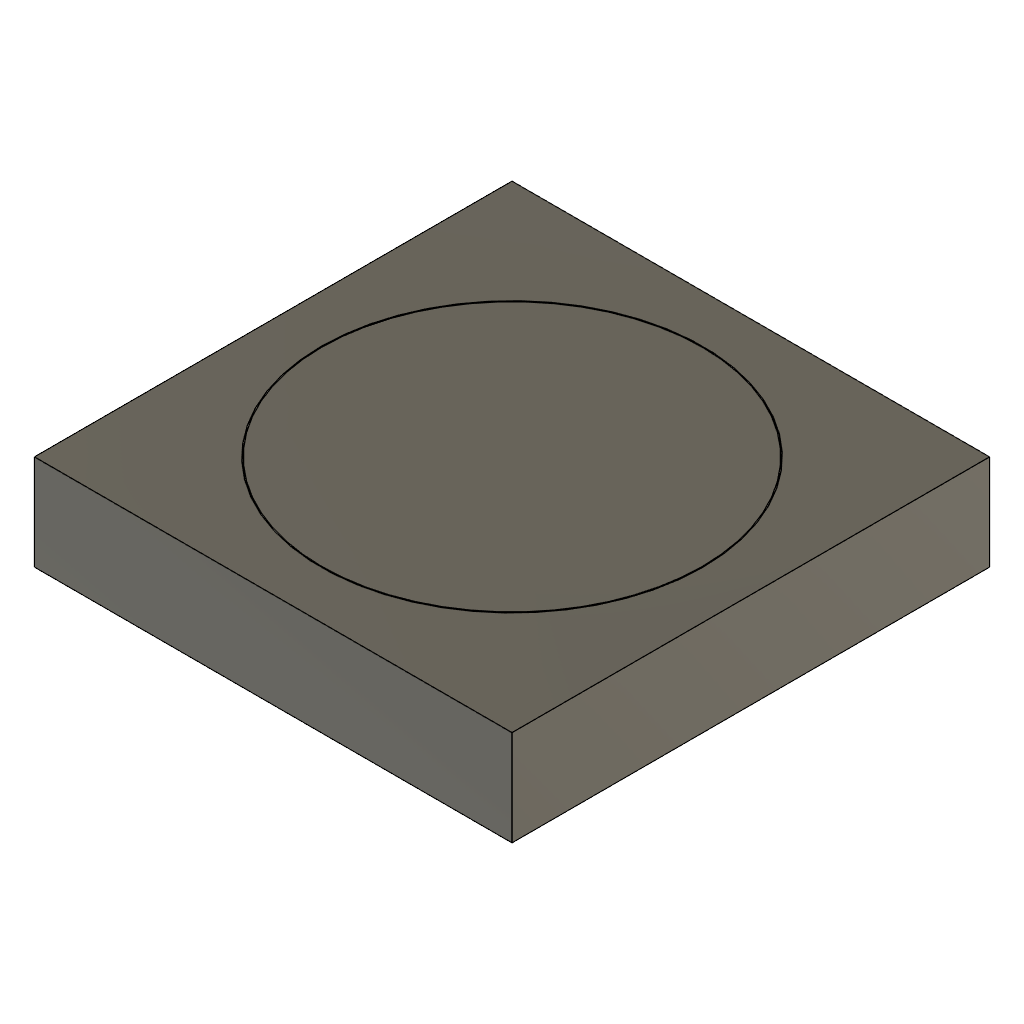
cubefinalfinalmaybev3 (Autodesk Fusion 360 design; units mm, degrees)
part number: 2026-09-11-18-23-56-695
Autodesk Fusion 360 part; units mm, degrees
sketch "Sketch1" plane through (0, 0, 0) normal (0, 0, 1) x (1, 0, 0)
  line L0 (-25, -25) -> (25, -25)
  line L1 (25, -25) -> (25, 25)
  line L2 (25, 25) -> (-25, 25)
  line L3 (-25, 25) -> (-25, -25)
  circle A0 centre (0, 0) radius 20
extrude "Extrude1" add sketch "Sketch1" along normal blind 10 makes body 1
sketch "Sketch2" plane through (0, 0, 0) normal (0, 0, 1) x (1, 0, 0)
  circle A0 centre (0, 0) radius 19.9
extrude "Extrude2" add sketch "Sketch2" along normal blind 10 separate body makes body 2
named bodies: "Cube", "Cylinder"
